Ball (Autodesk Fusion 360 design; units mm, degrees)
part number: 2026-10-17-16-36-14-796
Autodesk Fusion 360 part; units mm, degrees
sphere "SpherePrimitive1" add diameter 65 placed x (1, 0, 0) y (0, 1, 0) z (0, 0, 1) at (0, 0, 0)
